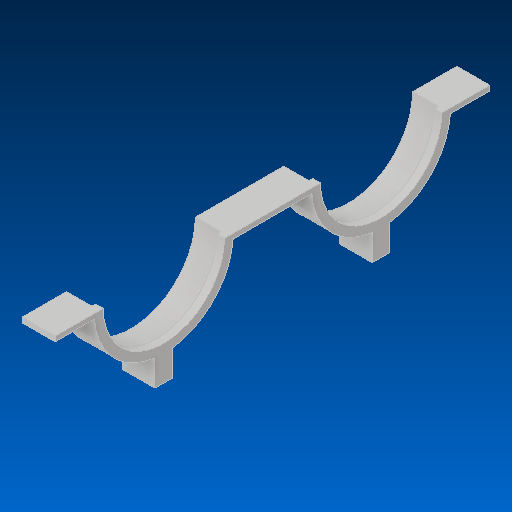
# Autodesk Inventor part: fork v5
Saved by Autodesk Inventor 2019 (Build 230136000, 136)
## iProperties
Created: 2019-04-16
Part Number: fork v5
Material: Generic
Document SubType Name: Modeling
Designer: Dell
Density: 1 g/cm^3
Appearance: Default
Author: Dell
Autodesk Inventor part; units mm, degrees
ref_plane "YZ Plane" through (0, 0, 0) normal (1, 0, 0) x (0, 1, 0)
ref_plane "XZ Plane" through (0, 0, 0) normal (0, 1, 0) x (-1, 0, 0)
ref_plane "XY Plane" through (0, 0, 0) normal (0, 0, 1) x (1, 0, 0)
sketch "Sketch1" plane through (0, 0, 0) normal (1, 0, 0) x (0, 1, 0)
  arc A0 (-17.0292, 25.5024) -> (-17.0292, -25.4976) centre (-17.0292, 0.0024) ccw
  line L0 (-44.3046, 3.5096) -> (-54.6362, 3.5096)
  line L1 (-54.6362, 3.5096) -> (-54.6362, -3.5048)
  line L2 (-54.6362, -3.5048) -> (-44.3046, -3.5048)
  line L3 (-44.5264, 0.3965) -> (-44.7792, 0.0024) construction
  line L4 (-44.7792, 0.0024) -> (-44.5264, -0.3917) construction
  line L5 (-17.0292, 27.5024) -> (-17.0292, 25.5024)
  line L6 (-17.0292, -25.4976) -> (-17.0292, -27.4976)
  arc A1 (-44.3046, -3.5048) -> (-17.0292, -27.4976) centre (-17.0292, 0.0024) ccw
  arc A2 (-17.0292, 27.5024) -> (-44.3046, 3.5096) centre (-17.0292, 0.0024) ccw
  dimension "d9" = 51
  dimension "d13" = 37.607
  dimension "d14" = 27.5
  constraints: 14 end point, 6 point on circle, 3 centre point, 2 vertical, 1 coincident, 1 collinear, 1 horizontal, 1 parallel, 1 perpendicular
  measures "d9" diameter of A0
  measures "d13" distance from line of L1 A0.centre
  measures "d14" vertical distance of L3.end L5.start
extrude "Extrusion1" add sketch "Sketch1" along normal blind 10
sketch "Sketch2" plane through (0, -17.0292, 27.5024) normal (0, 1, 0) x (1, 0, 0)
  line L0 (0, 53) -> (10, 53) projected
  line L1 (10, 53) -> (0, 53)
  line L2 (0, 53) -> (0, 70.5024)
  line L3 (0, 70.5024) -> (10, 70.5024)
  line L4 (10, 70.5024) -> (10, 53)
  line L5 (10, 0) -> (10, 23.9928) projected
  line L6 (10, 2) -> (0, 2)
  line L7 (0, 2) -> (0, -15.4976)
  line L8 (0, -15.4976) -> (10, -15.4976)
  line L9 (10, -15.4976) -> (10, 2)
  line L10 (0, 2) -> (10, 2) projected
  line L11 (0, 53) -> (0, 55) projected
  line L12 (0, 0) -> (0, 2) projected
  point P0 (0, 27.5024)
  dimension "d17" = 43
  dimension "d18" = 43
  constraints: 16 end point, 4 parallel, 3 collinear, 2 horizontal, 2 perpendicular, 2 point on line
  measures "d17" distance from line of L3 point (0, 27.502)
  measures "d18" distance from line of L8 point (0, 27.502)
extrude "Extrusion2" add sketch "Sketch2" against normal blind 2
mirror "Mirror1" about plane through (10, -17.0292, 43) normal (0, 0, 1) of "Extrusion1"
mirror "Mirror2" about plane through (10, -17.0292, 43) normal (0, 0, 1) of "Extrusion2"
sketch "Sketch4" plane through (0, -54.6362, -3.5048) normal (0, -1, 0) x (1, 0, 0)
  circle A0 centre (7.5, 3.5) radius 1.5
  line L0 (0, 0) -> (10, 0) projected
  line L1 (10, 7.0144) -> (10, 0) projected
  circle A1 centre (2.5, 89.4952) radius 1.5
  line L2 (0, 85.9952) -> (10, 85.9952) projected
  line L3 (0, 93.0096) -> (0, 85.9952) projected
  point P0 (0, 3.5048)
  dimension "d40" = 3
  dimension "d41" = 3.5
  dimension "d42" = 2.5
  dimension "d43" = 3
  dimension "d44" = 3.5
  dimension "d45" = 2.5
  constraints: 2 centre point
  measures "d40" diameter of A0
  measures "d41" distance from line of A0.centre L0
  measures "d42" distance from line of L1 A0.centre
  measures "d43" diameter of A1
  measures "d44" distance from line of A1.centre L2
  measures "d45" distance from line of A1.centre L3
hole "Hole2" at (2.5, -54.6362, 85.9904) at (7.5, -54.6362, -0.0048) direction (0, 1, 0) diameter 3 depth 5 tip angle 118
sketch "Sketch5" plane through (10, 0, 0) normal (1, 0, 0) x (0, 0, -1)
  line L0 (-25.5024, -17.0292) -> (-60.4976, -17.0292) projected
  arc A0 (-111.4976, -17.0292) -> (-60.4976, -17.0292) centre (-85.9976, -17.0292) ccw projected
  line L1 (-129, -17.0292) -> (-111.4976, -17.0292) projected
  line L2 (-129, -17.0292) -> (-129, -19.0292) projected
  line L3 (-129, -19.0292) -> (-113.4248, -19.0292) projected
  arc A1 (-113.4248, -19.0292) -> (-89.5048, -44.3046) centre (-85.9976, -17.0292) ccw projected
  line L4 (-89.5048, -54.6362) -> (-89.5048, -44.3046) projected
  line L5 (-82.4904, -54.6362) -> (-89.5048, -54.6362) projected
  line L6 (-82.4904, -44.3046) -> (-82.4904, -54.6362) projected
  arc A2 (-82.4904, -44.3046) -> (-58.5704, -19.0292) centre (-85.9976, -17.0292) ccw projected
  line L7 (-27.4296, -19.0292) -> (-58.5704, -19.0292) projected
  arc A3 (-27.4296, -19.0292) -> (-3.5096, -44.3046) centre (-0.0024, -17.0292) ccw projected
  line L8 (-3.5096, -44.3046) -> (-3.5096, -54.6362) projected
  line L9 (-3.5096, -54.6362) -> (3.5048, -54.6362) projected
  line L10 (3.5048, -54.6362) -> (3.5048, -44.3046) projected
  arc A4 (3.5048, -44.3046) -> (27.4248, -19.0292) centre (-0.0024, -17.0292) ccw projected
  line L11 (43, -19.0292) -> (27.4248, -19.0292) projected
  line L12 (43, -17.0292) -> (43, -19.0292) projected
  line L13 (25.4976, -17.0292) -> (43, -17.0292) projected
  arc A5 (-25.5024, -17.0292) -> (25.4976, -17.0292) centre (-0.0024, -17.0292) ccw projected
  arc A6 (-24.0024, -17.0292) -> (23.9976, -17.0292) centre (-0.0024, -17.0292) ccw
  arc A7 (-109.9976, -17.0292) -> (-61.9976, -17.0292) centre (-85.9976, -17.0292) ccw
  line L14 (-129, -17.0292) -> (43, -17.0292)
  point P0 (0, 0)
  dimension "d53" = 48
  dimension "d54" = 48
  constraints: 4 point on circle, 4 point on line, 2 centre point, 2 coincident, 2 end point, 1 horizontal
  measures "d53" diameter of A6
  measures "d54" diameter of A7
extrude "Extrusion3" add sketch "Sketch5" along normal blind 3 contours A5 L13 L12 L11 A4 L10 L9 L8 A3 L7 A2 L6 L5 L4 A1 L3 L2 L1 A0 L0 | L14 A6 A5 | A0 L14 A7
body "Solid1"
